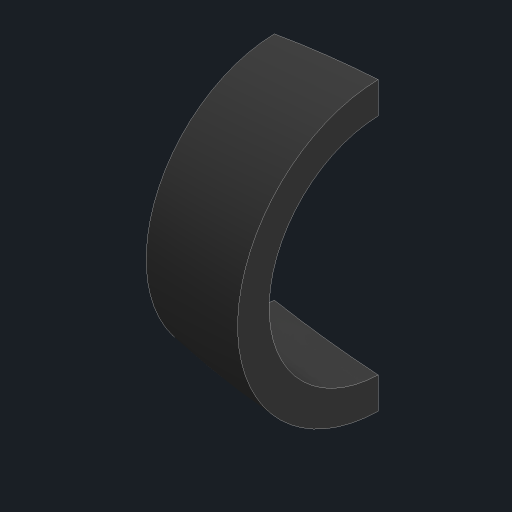
# Autodesk Inventor part: Rolete
Saved by Autodesk Inventor 2024.3 (Build 283343000, 343)
## iProperties
Created: 2025-01-03
Part Number: Rolete
Material: ABS plástico
Document SubType Name: Modeling
Designer: Cliente
Density: 26.1425 g/cm^3
Appearance: Borracha - Preta
Mass: 8.169 g
Surface Area: 4.43469 cm^2
Volume: 0.320471 cm^3
Author: Cliente
Autodesk Inventor part; units mm, degrees
ref_plane "YZ Plane" through (0, 0, 0) normal (1, 0, 0) x (0, 1, 0)
ref_plane "XZ Plane" through (0, 0, 0) normal (0, 1, 0) x (-1, 0, 0)
ref_plane "XY Plane" through (0, 0, 0) normal (0, 0, 1) x (1, 0, 0)
sketch "Esboço1" plane through (0, 0, 0) normal (0, 0, 1) x (1, 0, 0)
  circle A0 centre (0, 0) radius 59.25
  line L0 (0, 0) -> (0, 50)
  line L1 (-17.5, 50) -> (17.5, 50)
  line L2 (-17.5, 50) -> (-17.5, 56.6066)
  line L3 (17.5, 50) -> (17.5, 56.6066)
  line L4 (-17.5, 51.35) -> (17.5, 51.35)
  line L5 (-10.5, 58.3122) -> (-10.5, 51.35)
  line L6 (-3.5, 51.35) -> (-3.5, 59.1465)
  line L7 (3.5, 59.1465) -> (3.5, 51.35)
  line L8 (10.5, 58.3122) -> (10.5, 51.35)
  circle A1 centre (0, 0) radius 57.25
  point P0 (10.5, 56.2789)
  point P1 (3.5, 57.1429)
  point P2 (-3.5, 57.1429)
  point P3 (-10.5, 56.2789)
  dimension "d0" = 118.5
  dimension "d1" = 50
  dimension "d2" = 35
  dimension "d3" = 1.35
  dimension "d5" = 7
  dimension "d6" = 7
  dimension "d7" = 7
  dimension "d8" = 7
  dimension "d9" = 7
  dimension "d10" = 2
  constraints: 18 end point, 6 point on circle, 6 point on line, 3 parallel, 3 perpendicular, 2 centre point, 2 vertical, 1 coincident, 1 horizontal, 1 midpoint
  measures "d0" diameter of A0
  measures "d1" distance of L0.end L0.start
  measures "d2" distance of L1.start L1.end
  measures "d3" distance between parallel lines of L1 L4
  measures "d5" distance between parallel lines of L5 L6
  measures "d6" distance between parallel lines of L8 L7
  measures "d7" distance between parallel lines of L2 L5
  measures "d8" distance between parallel lines of L3 L8
  measures "d9" distance between parallel lines of L7 L6
  measures "d10" radial gap between concentric circles of A0 A1
revolve "Revolução1" add sketch "Esboço1" angle 180 about axis through (-17.5, 50, 0) along (1, 0, 0) contours A0 L6 A1 L5
sketch "Esboço2" plane through (-3.5, 57.1429, 0) normal (1, 0, 0) x (0, 0, -1)
  line L0 (0, 0) -> (0, 2.0036) projected
  arc A0 (0, 2.0036) -> (0, -16.2894) centre (0, -7.1429) ccw projected
  line L1 (0, -14.2858) -> (0, -16.2894) projected
  arc A1 (0, 0) -> (0, -14.2858) centre (0, -7.1429) ccw projected
  line L2 (0, -0.864) -> (0, 0) projected
  arc A2 (0, 0) -> (0, -14.2858) centre (0, -7.1429) ccw projected
  line L3 (0, -13.4218) -> (0, -14.2858) projected
  arc A3 (0, -0.864) -> (0, -13.4218) centre (0, -7.1429) ccw projected
  line L4 (0, -16.2894) -> (-0.2, -16.2894)
  line L5 (-0.2, -16.2894) -> (-0.2, 2.0014)
  point P0 (0, -57.1429)
  point P1 (0, -14.2858)
  point P2 (-0.2, -13.4186)
  point P3 (-0.2, -16.2873)
  point P4 (-0.2, -0.8672)
  dimension "d13" = 0.2
  constraints: 4 end point, 1 point on circle, 1 tangent, 1 vertical
  measures "d13" distance of L1.end L4.end
extrude "Extrusão1" cut sketch "Esboço2" against normal blind 10 contours A1 L5 A0 L0 | L2 A3 L5 A1 | L5 A3 L3 A1 | A1 L1 A0 L5
sketch "Esboço3" plane through (-3.5, 57.1401, 0.2) normal (0, 0, -1) x (-1, 0, 0)
  spline S0 degree 4 poles (0, 2.0042) (0.8802, 1.9521) (1.7593, 1.8826) (2.6369, 1.7956) (4.3879, 1.5868) (5.2614, 1.4651) (6.1322, 1.326) (7, 1.1697) knots 0 0 0 0 0 0.499999 0.499999 0.499999 1 1 1 1 1 projected
  line L0 (0, 0) -> (0, 2.0042) projected
  line L1 (7, 1.1697) -> (7, -0.8644) projected
  line L2 (7, -0.8644) -> (7, -13.4158) projected
  line L3 (0, 0) -> (0, -14.2802) projected
  spline S1 degree 4 poles (7, -15.4499) (6.1322, -15.6062) (5.2614, -15.7453) (4.3879, -15.867) (2.6369, -16.0758) (1.7593, -16.1628) (0.8802, -16.2324) (0, -16.2845) knots 0 0 0 0 0 0.500001 0.500001 0.500001 1 1 1 1 1 projected
  line L4 (7, -13.4158) -> (7, -15.4499) projected
  line L5 (0, -16.2845) -> (0, -14.2802) projected
  line L6 (0.2, 1.9921) -> (0.2, -16.2723)
  line L7 (6.8, -15.4856) -> (6.8, 1.2053)
  point P0 (-3.5, -57.1401)
  point P1 (0, 0)
  dimension "d16" = 0.2
  dimension "d17" = 0.2
  constraints: 4 end point, 1 parallel, 1 vertical, 10 other
  measures "d16" distance between parallel lines of L7 L2
  measures "d17" distance between parallel lines of L3 L6
extrude "Extrusão2" cut sketch "Esboço3" against normal blind 10 contours S0 L6 S1 L5 L3 L0 | S0 L1 L2 L4 S1 L7
equation "\"d6\" = d5"
equation "\"d8\" = d7"
